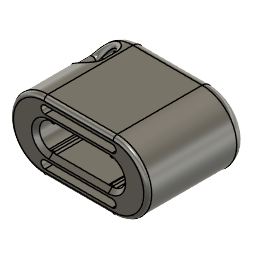
KeyModMini_Cover (Autodesk Fusion 360 design; units mm, degrees)
Autodesk Fusion 360 part; units mm, degrees
sketch "草图1" plane through (0, 0, 0) normal (0, 0, 1) x (1, 0, 0)
  line L0 (-3.5, -3.5) -> (3.5, -3.5)
  arc A0 (3.5, -3.5) -> (3.5, 3.5) centre (3.5, 0) ccw
  line L1 (3.5, 3.5) -> (-3.5, 3.5)
  arc A1 (-3.5, 3.5) -> (-3.5, -3.5) centre (-3.5, 0) ccw
  line L2 (-3.5, 0) -> (3.5, 0) construction
  dimension "d1" = 7
  dimension "d2" = 7
  constraint tangent L0 A0
  constraint tangent A0 L1
  constraint parallel L0 L1
  constraint tangent L1 A1
  constraint tangent L0 A1
  constraint horizontal L2
  constraint midpoint L2 origin
  measures "d1" distance of A1.centre A0.centre
  measures "d2" distance of L0 L1
extrude "拉伸1" add sketch "草图1" along normal blind 10
sketch "草图2" plane through (0, 0, 10) normal (0, 0, 1) x (1, 0, 0)
  arc A0 (-3.5, 3.5) -> (-3.5, -3.5) centre (-3.5, 0) ccw
  line L0 (-3.5, -3.5) -> (3.5, -3.5)
  arc A1 (3.5, -3.5) -> (3.5, 3.5) centre (3.5, 0) ccw
  line L1 (3.5, 3.5) -> (-3.5, 3.5)
  line L2 (-3, -1.35) -> (3, -1.35)
  arc A2 (3, -1.35) -> (3, 1.35) centre (3, 0) ccw
  line L3 (3, 1.35) -> (-3, 1.35)
  arc A3 (-3, 1.35) -> (-3, -1.35) centre (-3, 0) ccw
  line L4 (-3, 0) -> (3, 0) construction
  line L5 (-4.35, 0) -> (4.35, 0) construction
  dimension "d5" = 2.7
  dimension "d6" = 8.7
  constraint tangent L2 A2
  constraint tangent A2 L3
  constraint parallel L2 L3
  constraint tangent L3 A3
  constraint tangent L2 A3
  constraint horizontal L4
  constraint midpoint L4 origin
  constraint midpoint A3 L5.start
  constraint midpoint A2 L5.end
  measures "d5" distance of L2 L3
  measures "d6" distance of L5.start L5.end
extrude "拉伸2" cut sketch "草图2" against normal blind 9 contours L2 A2 L3 A3
chamfer "倒角1" distance 0.4 angle 45 4 edges at (0, -1.35, 10) (-4.35, 0, 10) (0, 1.35, 10) (4.35, 0, 10) tangent chain off
sketch "草图3" plane through (0, 0, 1) normal (0, 0, 1) x (1, 0, 0)
  arc A0 (-3, 1.35) -> (-3, -1.35) centre (-3, 0) ccw
  line L0 (-3, -1.35) -> (3, -1.35)
  arc A1 (3, -1.35) -> (3, 1.35) centre (3, 0) ccw
  line L1 (3, 1.35) -> (-3, 1.35)
  circle A2 centre (-3, -1.35) radius 0.175
  circle A3 centre (-3, 1.35) radius 0.175
  circle A4 centre (3, 1.35) radius 0.175
  circle A5 centre (3, -1.35) radius 0.175
  dimension "d27" = 0.35
  dimension "d28" = 0.35
  dimension "d29" = 0.35
  dimension "d30" = 0.35
  constraint coincident A0.end L0.start
  constraint coincident A0.start L1.end
  constraint coincident A1.end L1.start
  constraint coincident L0.end A1.start
  measures "d27" diameter of A2
  measures "d28" diameter of A3
  measures "d29" diameter of A4
  measures "d30" diameter of A5
extrude "拉伸3" add sketch "草图3" along normal blind 8.6 contours A0 L1 A3 | A0 L0 A2 | A1 L1 A4 | L0 A1 A5 picked at (-3.0386, 1.2945) picked at (-3.0386, -1.2945) picked at (3.0386, 1.2945) picked at (3.0386, -1.2945)
fillet "圆角5" radius 0.3 8 edges at (-3.1746, 1.3387, 5.3) (-2.825, 1.35, 5.3) (-2.825, -1.35, 5.3) (-3.1746, -1.3387, 5.3) (2.825, -1.35, 5.3) (3.1746, -1.3387, 5.3) (3.1746, 1.3387, 5.3) (2.825, 1.35, 5.3)
fillet "圆角1" radius 1 4 edges at (7, 0, 0) (0, 3.5, 0) (-7, 0, 0) (0, -3.5, 0)
fillet "圆角3" radius 0.4 4 edges at (0, 3.5, 10) (-7, 0, 10) (0, -3.5, 10) (7, 0, 10)
sketch "草图4" plane through (0, 3.5, 0) normal (0, 1, 0) x (-1, 0, 0)
  line L0 (3.5, 9.6) -> (-3.5, 9.6)
  line L1 (-3.5, 9.6) -> (-3.5, 1)
  line L2 (-3.5, 1) -> (3.5, 1)
  line L3 (3.5, 1) -> (3.5, 9.6)
  line L4 (5.85, 2.35) -> (5.85, 3.65)
  arc A0 (5.85, 3.65) -> (4.15, 3.65) centre (5, 3.65) ccw
  line L5 (4.15, 3.65) -> (4.15, 2.35)
  arc A1 (4.15, 2.35) -> (5.85, 2.35) centre (5, 2.35) ccw
  line L6 (5, 2.35) -> (5, 3.65) construction
  line L7 (-3.5, 0) -> (3.5, 0)
  point P0 (5, 3)
  dimension "d37" = 1.3
  dimension "d39" = 3
  dimension "d40" = 1.5
  dimension "d43" = 1.7
  constraint tangent L4 A0
  constraint tangent A0 L5
  constraint parallel L4 L5
  constraint tangent L5 A1
  constraint tangent L4 A1
  constraint vertical L6
  constraint midpoint L6 P0
  measures "d37" distance of A1.centre A0.centre
  measures "d39" distance of P0 L7
  measures "d40" distance of L3 P0
  measures "d43" distance of L4 L5
extrude "拉伸4" cut sketch "草图4" against normal blind 10 contours L4 A0 L5 A1
fillet "圆角6" radius 0.4 8 edges at (-5.0398, 3.1431, 4.499) (-5.85, 2.5937, 3) (-5.0398, 3.1431, 1.501) (-4.15, 3.4391, 3) (-5.85, -2.5937, 3) (-5.0398, -3.1431, 4.499) (-4.15, -3.4391, 3) (-5.0398, -3.1431, 1.501)
sketch "草图5" plane through (0, 0, 10) normal (0, 0, 1) x (1, 0, 0)
  line L0 (3, -1.75) -> (-3, -1.75)
  arc A0 (-3, 1.75) -> (-3, -1.75) centre (-3, 0) ccw
  line L1 (-3, 1.75) -> (3, 1.75)
  arc A1 (3, -1.75) -> (3, 1.75) centre (3, 0) ccw
  line L2 (3.5, 3.1) -> (-3.5, 3.1)
  arc A2 (-3.5, 3.1) -> (-3.5, -3.1) centre (-3.5, 0) ccw
  line L3 (-3.5, -3.1) -> (3.5, -3.1)
  arc A3 (3.5, -3.1) -> (3.5, 3.1) centre (3.5, 0) ccw
  line L4 (-6.6, 0) -> (6.6, 0) construction
  line L5 (-3.4, 2) -> (3.4, 2)
  arc A4 (3.4, 2) -> (3.4, 2.8) centre (3.4, 2.4) ccw
  line L6 (3.4, 2.8) -> (-3.4, 2.8)
  arc A5 (-3.4, 2.8) -> (-3.4, 2) centre (-3.4, 2.4) ccw
  line L7 (-3.4, 2.4) -> (3.4, 2.4) construction
  line L8 (0, 3.1) -> (0, -3.1) construction
  line L9 (-3.4, -2) -> (3.4, -2)
  arc A6 (3.4, -2.8) -> (3.4, -2) centre (3.4, -2.4) ccw
  arc A7 (-3.4, -2) -> (-3.4, -2.8) centre (-3.4, -2.4) ccw
  line L10 (3.4, -2.8) -> (-3.4, -2.8)
  line L11 (-3.4, -2.4) -> (3.4, -2.4) construction
  point P0 (0, 2.4)
  point P1 (0, -2.4)
  dimension "d46" = 6.8
  dimension "d47" = 0.8
  dimension "d48" = 2.4
  constraint midpoint A2 L4.start
  constraint midpoint A3 L4.end
  constraint tangent L5 A4
  constraint tangent A4 L6
  constraint parallel L5 L6
  constraint tangent L6 A5
  constraint tangent L5 A5
  constraint parallel L2 L7
  constraint midpoint L7 P0
  constraint midpoint L2 L8.start
  constraint midpoint L3 L8.end
  constraint symmetric L4 L5.start L9.start
  constraint symmetric L4 L5.end L9.end
  constraint symmetric L4 A4.end A6.start
  constraint symmetric L4 L6.end A7.end
  constraint symmetric L4 A4 A6
  constraint symmetric L4 A5 A7
  constraint symmetric L4 P0 P1
  constraint coincident P0 L8
  measures "d46" distance of A5.centre A4.centre
  measures "d47" distance of L5 L6
  measures "d48" distance of L4 P0
extrude "拉伸5" cut sketch "草图5" against normal blind 9 contours L5 A4 L6 A5 | L9 A6 A7 L10
named bodies: "Keymod mini保护盖"
